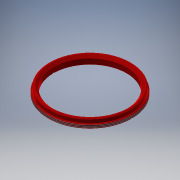
# Autodesk Inventor part: 15-0012-0321
Saved by Autodesk Inventor 2016 SP2 (Build 200236200, 236)
## iProperties
Created: 2017-10-26
Part Number: 15-0012-0321
Material: Plastic (PEEK)
Document SubType Name: Modeling
Designer: jellerm1
Density: 1.32 g/cm^3
Appearance: Smooth - Red
Project: Quantum Gas Microscope
Cost Center: 15-0012
User Status: Work in Progress
Authority: Georgios Siviloglou
RuleStatus: InUse
Category: IOP
Company: Universiteit van Amsterdam
BeforeDocSave0: Open Form
Author: jellerm1
Title: Quantum Gas Microscope
Revision Number: A
Autodesk Inventor part; units mm, degrees
ref_plane "YZ Plane" through (0, 0, 0) normal (1, 0, 0) x (0, 1, 0)
ref_plane "XZ Plane" through (0, 0, 0) normal (0, 1, 0) x (-1, 0, 0)
ref_plane "XY Plane" through (0, 0, 0) normal (0, 0, 1) x (1, 0, 0)
sketch "Sketch1" plane through (0, 0, 0) normal (0, 0, 1) x (1, 0, 0)
  line L0 (0, 17.5122) -> (0, -17.5122) construction
  line L1 (-29.4153, 0) -> (4.9025, 0) construction
  point P0 (0, 0)
sketch "Sketch2" plane through (0, 0, 0) normal (1, 0, 0) x (0, 1, 0)
  line L0 (26, -5) -> (22.5, -5)
  line L1 (22.5, -5) -> (22.5, 0)
  line L2 (22.5, 0) -> (25.25, 0)
  line L3 (25.25, 0) -> (25.25, -2.5)
  line L4 (25.25, -2.5) -> (26, -2.5)
  line L5 (26, -2.5) -> (26, -5)
  line L6 (0, 1) -> (0, -6) projected
  line L7 (-5.2, 0) -> (31.2, 0) construction
  point P0 (0, 0)
  dimension "d0" = 52
  dimension "d1" = 45
  dimension "d2" = 50.5
  dimension "d3" = 0
  dimension "d4" = 5
  dimension "d5" = 2.5
  constraints: 12 end point, 3 perpendicular, 2 horizontal
  measures "d0" diameter of L5 L6
  measures "d1" diameter of L1 L6
  measures "d2" diameter of L3 L6
  measures "d3" distance between parallel lines of L7 L2
  measures "d4" distance between parallel lines of L0 L2
  measures "d5" distance of L2.end L3.end
revolve "Revolution1" add sketch "Sketch2" angle 360 about axis through (0, 0, 0) along (0, 0, -1)
chamfer "Chamfer1" distance 0.3 angle 45 3 edges at (0, -26, -5) (0, -26, -2.5) (0, -22.5, -5)
thread "Thread1" size "M4x0.7" class "6g" standard "ISO Metric profile" full length
sketch "Sketch3" plane through (0, 0, -5) normal (0, 0, -1) x (-1, 0, 0)
  line L0 (0, -36.4) -> (0, 36.4) construction
  line L1 (-36.4, 0) -> (36.4, 0) construction
  line L2 (-15, 0.5) -> (-30, 0.5)
  line L3 (-30, 0.5) -> (-30, -0.5)
  line L4 (-30, -0.5) -> (-15, -0.5)
  line L5 (-15, -0.5) -> (-15, 0.5)
  line L6 (-15, 0.5) -> (-30, -0.5) construction
  line L7 (-30, 0.5) -> (-15, -0.5) construction
  point P0 (0, 0)
  point P1 (24.5127, 0)
  point P2 (-22.5, 0)
  dimension "d12" = 24.5127
  dimension "d19" = 15
  dimension "d20" = 1
  dimension "d21" = 15
  constraints: 12 end point, 2 midpoint, 2 parallel, 2 point on line, 1 horizontal, 1 perpendicular
  measures "d12" distance from line of L0 point (24.513, 0)
  measures "d19" distance of L4.end L3.end
  measures "d20" distance of L3.end L2.end
  measures "d21" distance between parallel lines of L5 L0
chamfer "Chamfer2" distance 0.5 angle 45 1 edges at (0, -25.25, 0)
chamfer "Chamfer3" distance 1.5 angle 45 1 edges at (0, -22.5, 0)
extrude "Extrusion1" cut sketch "Sketch3" against normal blind 0.6
pattern_circular "Circular Pattern1" count 2 over 360 about axis through (0, 0, -2.5) along (0, 0, -1) of "Extrusion1"
equation "\"d5\" = 0.5 * d4"
body "Solid1"
